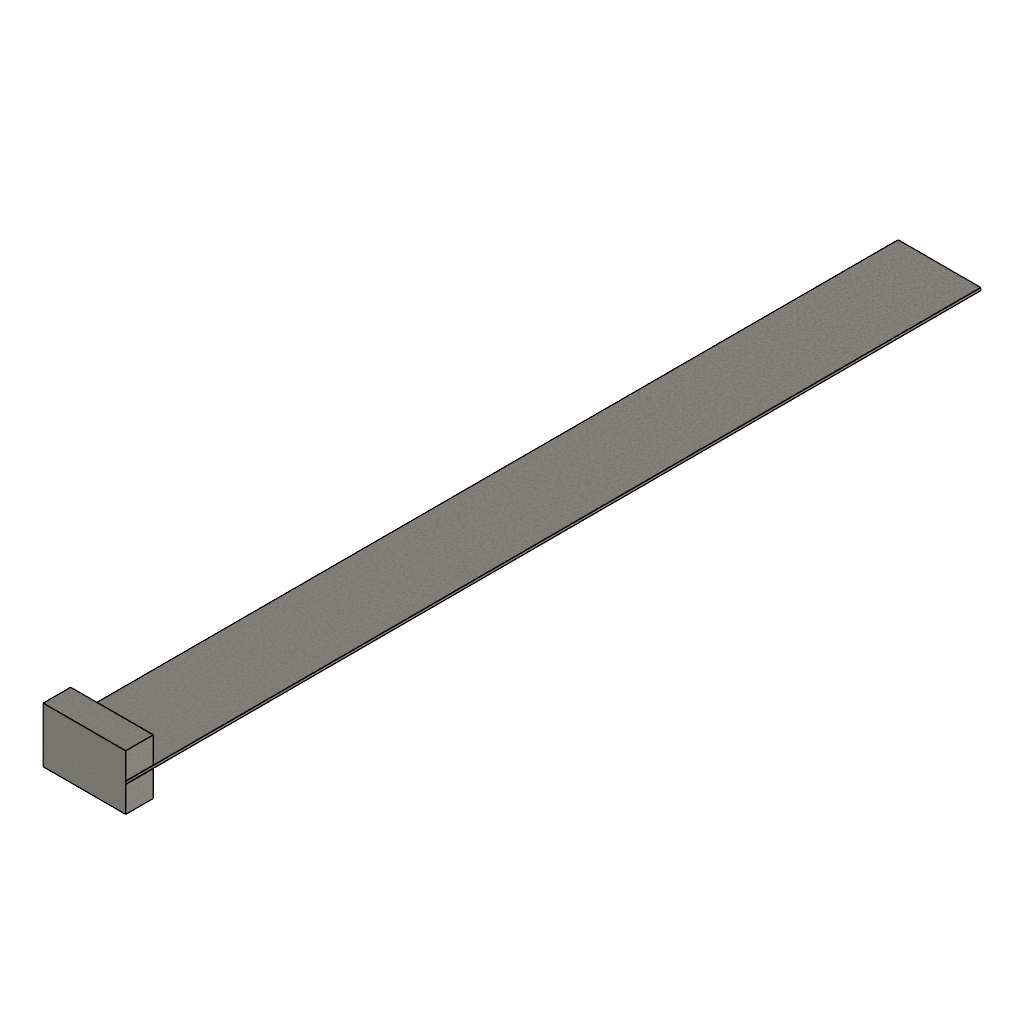
poutre (Autodesk Fusion 360 design; units mm, degrees)
part number: 2026-10-24-03-33-39-944
Autodesk Fusion 360 part; units mm, degrees
sketch "Esquisse1" plane through (0, 0, 0) normal (0, 0, 1) x (1, 0, 0)
  line L0 (0, 0) -> (30, 0)
  line L1 (30, 0) -> (30, 300)
  line L2 (30, 300) -> (0, 300)
  line L3 (0, 300) -> (0, 0)
  dimension "d1" = 30
  dimension "d2" = 300
  constraint horizontal L0
  constraint vertical L1
  constraint horizontal L2
  constraint vertical L3
  constraint coincident L0.start L3.end
  measures "d1" distance of L0.start L0.end
  measures "d2" distance of L0.start L2.end
extrude "Extrusion1" add sketch "Esquisse1" along normal blind 1
sketch "Esquisse2" plane through (0, 0, 0) normal (0, -1, 0) x (1, 0, 0)
  line L0 (0, 0) -> (30, 0)
  line L1 (30, 0) -> (30, 1)
  line L2 (30, 1) -> (0, 1)
  line L3 (0, 1) -> (0, 0)
  line L4 (-0.0047, 10.5) -> (29.9437, 10.5)
  line L5 (29.9437, 10.5) -> (29.9437, -9.5)
  line L6 (29.9437, -9.5) -> (-0.0047, -9.5)
  line L7 (-0.0047, -9.5) -> (-0.0047, 10.5)
  point P0 (0, 0.5)
  point P1 (30, 0.5)
  dimension "d5" = 10
  dimension "d6" = 10
  constraint horizontal L4
  constraint vertical L5
  constraint horizontal L6
  constraint vertical L7
  constraint midpoint L3 P0
  constraint midpoint L1 P1
  measures "d5" distance of L4 P1
  measures "d6" vertical distance of L5.end P1
extrude "Extrusion2" add sketch "Esquisse2" along normal blind 10
